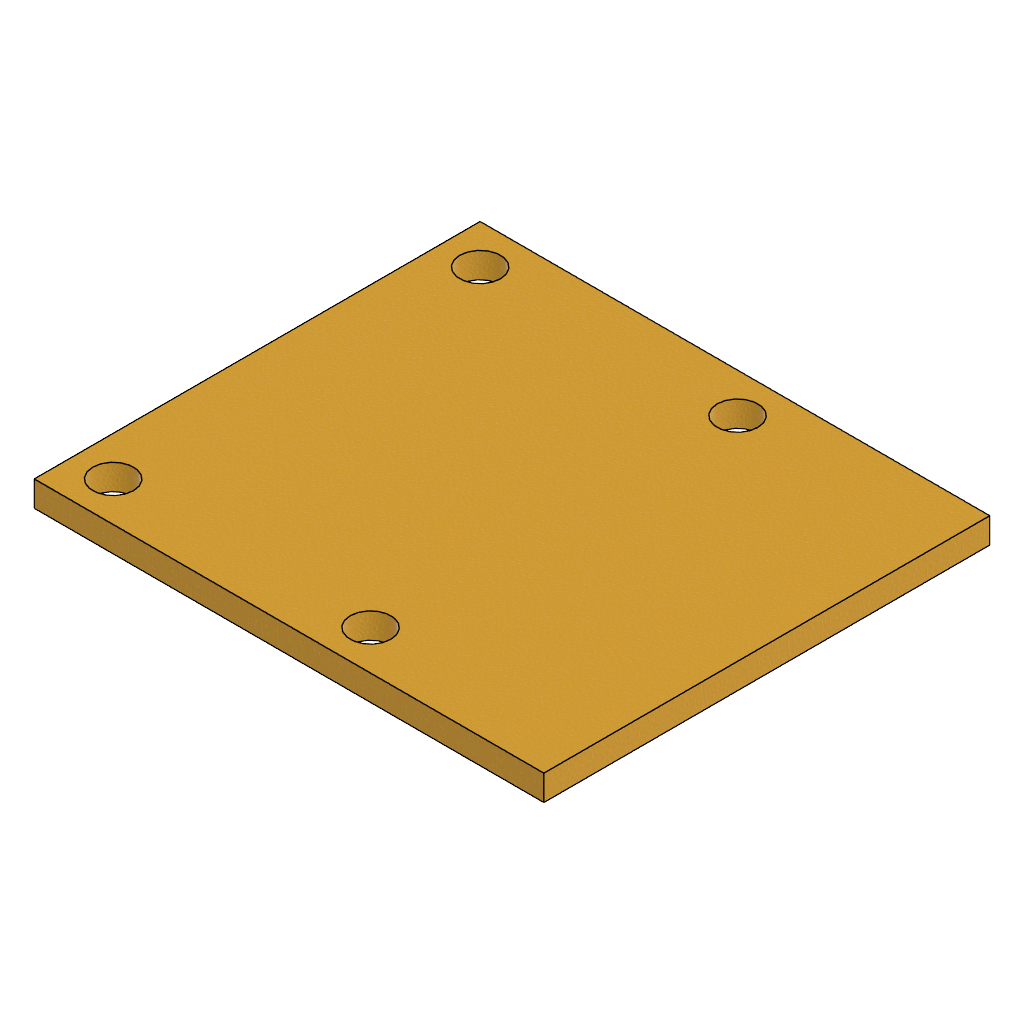
00-19 Perfboard DC-DC converter support Placeholder (Autodesk Fusion 360 design; units mm, degrees)
part number: 2026-11-09-11-33-29-053
Autodesk Fusion 360 part; units mm, degrees
sketch "Sketch1" plane through (0, 0, 0) normal (0, 0, 1) x (1, 0, 0)
  line L0 (0, 0) -> (40, 0)
  line L1 (40, 0) -> (40, 35)
  line L2 (40, 35) -> (0, 35)
  line L3 (0, 35) -> (0, 0)
  circle A0 centre (3.1, 31.9) radius 1.6
  circle A1 centre (3.1, 3.1) radius 1.6
  circle A2 centre (23.3, 3.1) radius 1.6
  circle A3 centre (23.3, 31.9) radius 1.6
  dimension "d1" = 35
  dimension "d2" = 40
  dimension "d3" = 3.2
  dimension "d4" = 28.8
  dimension "d5" = 20.2
  dimension "d6" = 3.1
  dimension "d7" = 3.1
  constraint horizontal L0
  constraint vertical L1
  constraint horizontal L2
  constraint vertical L3
  constraint coincident L0.start L3.end
  constraint equal A0 A1
  constraint equal A0 A3
  constraint equal A2 A3
  constraint horizontal A1.centre A2.centre
  constraint vertical A0.centre A1.centre
  constraint horizontal A0.centre A3.centre
  constraint vertical A2.centre A3.centre
  measures "d1" distance of L0.start L2.end
  measures "d2" distance of L1.end L2.end
  measures "d3" diameter of A1
  measures "d4" distance of A0.centre A1.centre
  measures "d5" distance of A1.centre A2.centre
  measures "d6" distance of L3 A1.centre
  measures "d7" distance of L0 A1.centre
extrude "Extrude1" add sketch "Sketch1" along normal blind 2
